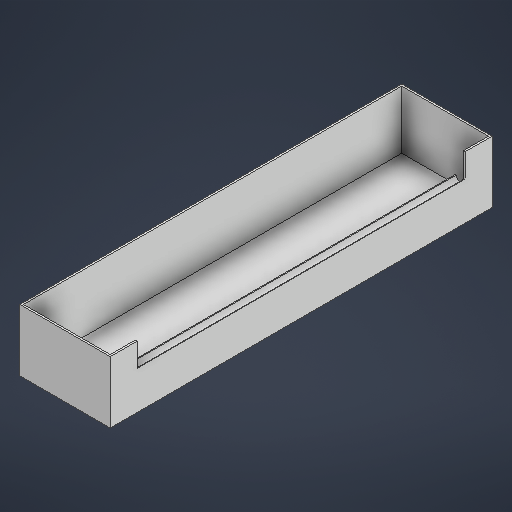
# Autodesk Inventor part: Container_section
Saved by Autodesk Inventor 2026.2 (Build 302298010, 298A)
## iProperties
Created: 2026-09-15
Part Number: Container_section
Material: Generic
Document SubType Name: Modeling
Designer: User
Density: 1 g/cm^3
Appearance: Default
Author: User
Autodesk Inventor part; units mm, degrees
ref_plane "YZ Plane" through (0, 0, 0) normal (1, 0, 0) x (0, 1, 0)
ref_plane "XZ Plane" through (0, 0, 0) normal (0, 1, 0) x (-1, 0, 0)
ref_plane "XY Plane" through (0, 0, 0) normal (0, 0, 1) x (1, 0, 0)
sketch "Sketch1" plane through (0, 0, 0) normal (0, 1, 0) x (-1, 0, 0)
  line L0 (49, 207) -> (-49, 207)
  line L1 (-49, 207) -> (-49, -207)
  line L2 (-49, -207) -> (49, -207)
  line L3 (49, -207) -> (49, 207)
  line L4 (49, 207) -> (-49, -207) construction
  line L5 (-49, 207) -> (49, -207) construction
  point P0 (0, 0)
  dimension "d0" = 98
  dimension "d1" = 414
  constraints: 12 end point, 2 midpoint, 2 parallel, 1 horizontal, 1 perpendicular
  measures "d0" distance of L2.end L1.end
  measures "d1" distance of L1.end L0.end
extrude "Extrusion1" add sketch "Sketch1" along normal blind 67
sketch "Sketch2" plane through (0, 67, 0) normal (0, 1, 0) x (1, 0, 0)
  line L0 (47, -205) -> (-47, -205)
  line L1 (-47, -205) -> (-47, 205)
  line L2 (-47, 205) -> (47, 205)
  line L3 (47, 205) -> (47, -205)
  line L4 (47, -205) -> (-47, 205) construction
  line L5 (-47, -205) -> (47, 205) construction
  point P0 (0, 0)
  dimension "d4" = 94
  dimension "d5" = 410
  constraints: 12 end point, 2 midpoint, 2 parallel, 1 horizontal, 1 perpendicular
  measures "d4" distance of L1.end L2.end
  measures "d5" distance of L0.end L1.end
extrude "Extrusion2" cut sketch "Sketch2" against normal blind 63
sketch "Sketch5" plane through (0, 67, 0) normal (0, 1, 0) x (1, 0, 0)
  line L0 (49, 207) -> (-49, 207) projected
  line L1 (49, 207) -> (49, 178)
  line L2 (49, 207) -> (78, 207) construction
  line L3 (49, -207) -> (49, 207) projected
  line L4 (49, -207) -> (49, -178)
  line L5 (49, -178) -> (47, -178)
  line L6 (47, 205) -> (47, -205) projected
  line L7 (47, -178) -> (47, 178)
  line L8 (47, 178) -> (49, 178)
  line L9 (49, 178) -> (49, -178)
  point P0 (0, 0)
  dimension "d20" = 29
  dimension "d21" = 90
  dimension "d22" = 29
  constraints: 14 end point, 3 point on line, 2 horizontal, 2 perpendicular, 1 collinear, 1 vertical
  measures "d20" distance of L0.start L1.end
  measures "d21" angle of L1 L2
  measures "d22" distance of L3.start L4.end
extrude "Extrusion4" cut sketch "Sketch5" against normal blind 27
sketch "Sketch6" plane through (49, 67, 178) normal (0, 0, -1) x (-1, 0, 0)
  line L0 (2, 0) -> (2, -27) projected
  line L1 (2, -27) -> (0, -25.5996)
  line L2 (0, -27) -> (0, 0) projected
  line L3 (2, -27) -> (4.4415, -27) construction
  line L4 (0, -27) -> (2, -27) projected
  line L5 (0, -25.5996) -> (0, -27)
  line L6 (0, -27) -> (2, -27)
  point P0 (49, -67)
  dimension "d25" = 145
  constraints: 8 end point, 2 perpendicular, 1 equal length, 1 horizontal, 1 point on line
  measures "d25" angle of L3 L1
extrude "Extrusion5" add sketch "Sketch6" along normal blind 356
sketch "Sketch7" plane through (49, 67, 178) normal (0, 0, -1) x (-1, 0, 0)
  line L0 (2, 0) -> (2, -27) projected
  line L1 (11, -35) -> (2, -35)
  line L2 (2, -35) -> (2, -27)
  arc A0 (2, -27) -> (10, -27) centre (6, -27) ccw
  line L3 (10, -27) -> (11, -27)
  line L4 (98, -67) -> (0, -67) projected
  line L5 (11, -27) -> (11, -35)
  point P0 (49, -67)
  dimension "d35" = 8
  dimension "d36" = 1
  constraints: 8 end point, 2 point on circle, 1 centre point, 1 collinear, 1 parallel, 1 perpendicular
  measures "d35" diameter of A0
  measures "d36" distance of L3.start L3.end
extrude "Extrusion6" add sketch "Sketch7" along normal blind 356
body "Solid1"
